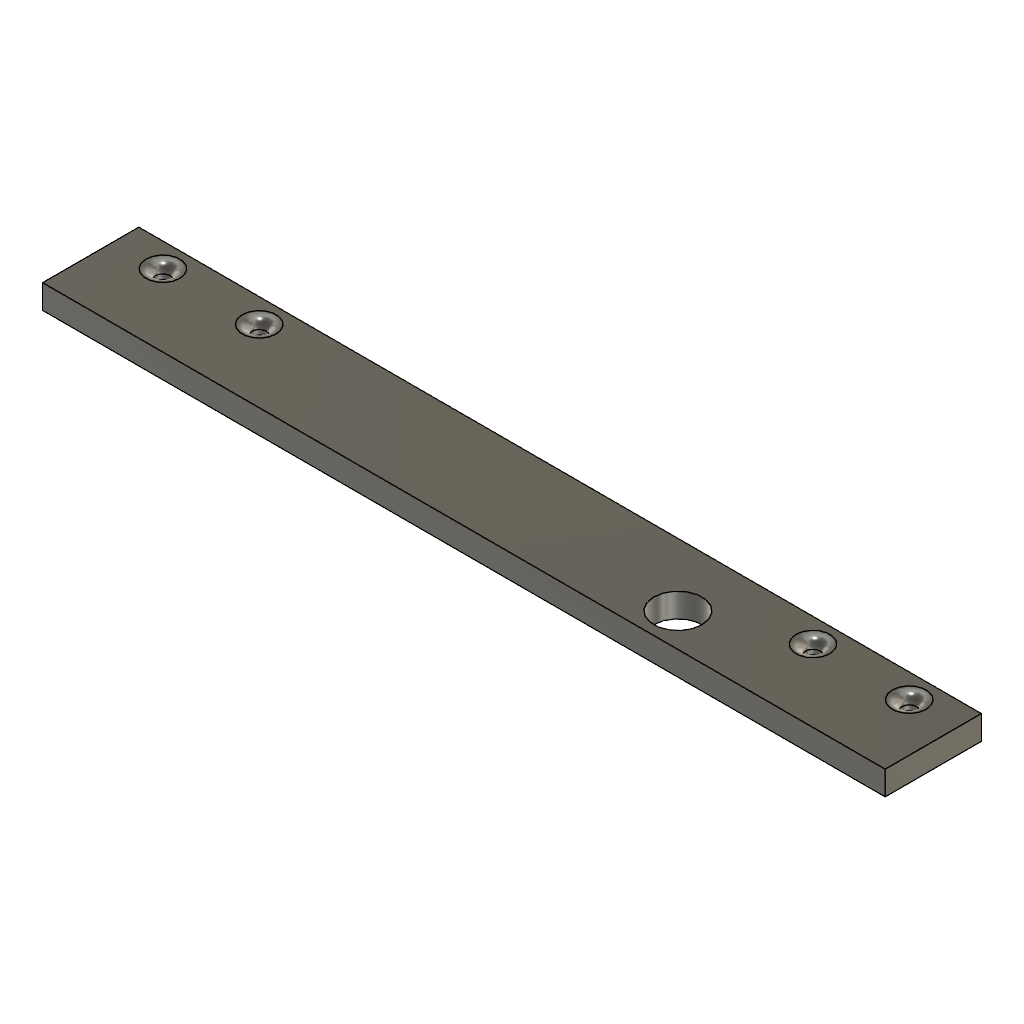
Soporte_luz_y_riego_x2 (Autodesk Fusion 360 design; units mm, degrees)
part number: 2026-09-25-16-41-54-505
Autodesk Fusion 360 part; units mm, degrees
sketch "Boceto1" plane through (0, 0, 0) normal (0, 0, 1) x (1, 0, 0)
  line L0 (0, 0) -> (175, 0)
  line L1 (175, 0) -> (175, 20)
  line L2 (175, 20) -> (0, 20)
  line L3 (0, 20) -> (0, 0)
  line L4 (0, 15) -> (175, 15)
  circle A0 centre (10, 15) radius 1.5
  circle A1 centre (30, 15) radius 1.5
  circle A2 centre (165, 15) radius 1.5
  circle A3 centre (125, 6.9538) radius 5
  line L5 (165, 15) -> (145, 15)
  circle A4 centre (145, 15) radius 1.5
  dimension "d1" = 175
  dimension "d2" = 20
  dimension "d3" = 3
  dimension "d5" = 3
  dimension "d6" = 3
  dimension "d7" = 10
  dimension "d8" = 20
  dimension "d9" = 10
  dimension "d10" = 3
  dimension "d11" = 20
  dimension "d12" = 10
  dimension "d13" = 50
  constraint horizontal L0
  constraint vertical L1
  constraint horizontal L2
  constraint vertical L3
  constraint coincident L0.start L3.end
  constraint coincident L3 L4.start
  constraint coincident L1 L4.end
  constraint perpendicular L1 L4
  constraint coincident L4 A0.centre
  constraint coincident L4 A1.centre
  constraint coincident L4 A2.centre
  constraint coincident A2.centre L5.start
  constraint coincident L4 L5.end
  constraint coincident L5.end A4.centre
  measures "d1" distance of L0.start L0.end
  measures "d2" distance of L0.end L1.end
  measures "d3" diameter of A2
  measures "d5" diameter of A1
  measures "d6" diameter of A0
  measures "d7" distance of L3 A0.centre
  measures "d8" distance of A0.centre A1.centre
  measures "d9" distance of L1 A2.centre
  measures "d10" diameter of A4
  measures "d11" distance of A2.centre L5.end
  measures "d12" diameter of A3
  measures "d13" distance of L1 A3.centre
extrude "Extruir1" add sketch "Boceto1" along normal blind 5 contours L0 L1 L3 L4 A0 A1 A2 L5 A4 | L1 L2 L3 L4 A0 A1 A2 L5 A4
fillet "Empalme1" radius 2 8 edges at (163.6015, 15.5424, 5) (143.6015, 15.5424, 5) (28.6015, 15.5424, 5) (8.6015, 15.5424, 5) (163.6015, 15.5424, 0) (143.6015, 15.5424, 0) (28.6015, 15.5424, 0) (8.6015, 15.5424, 0)
